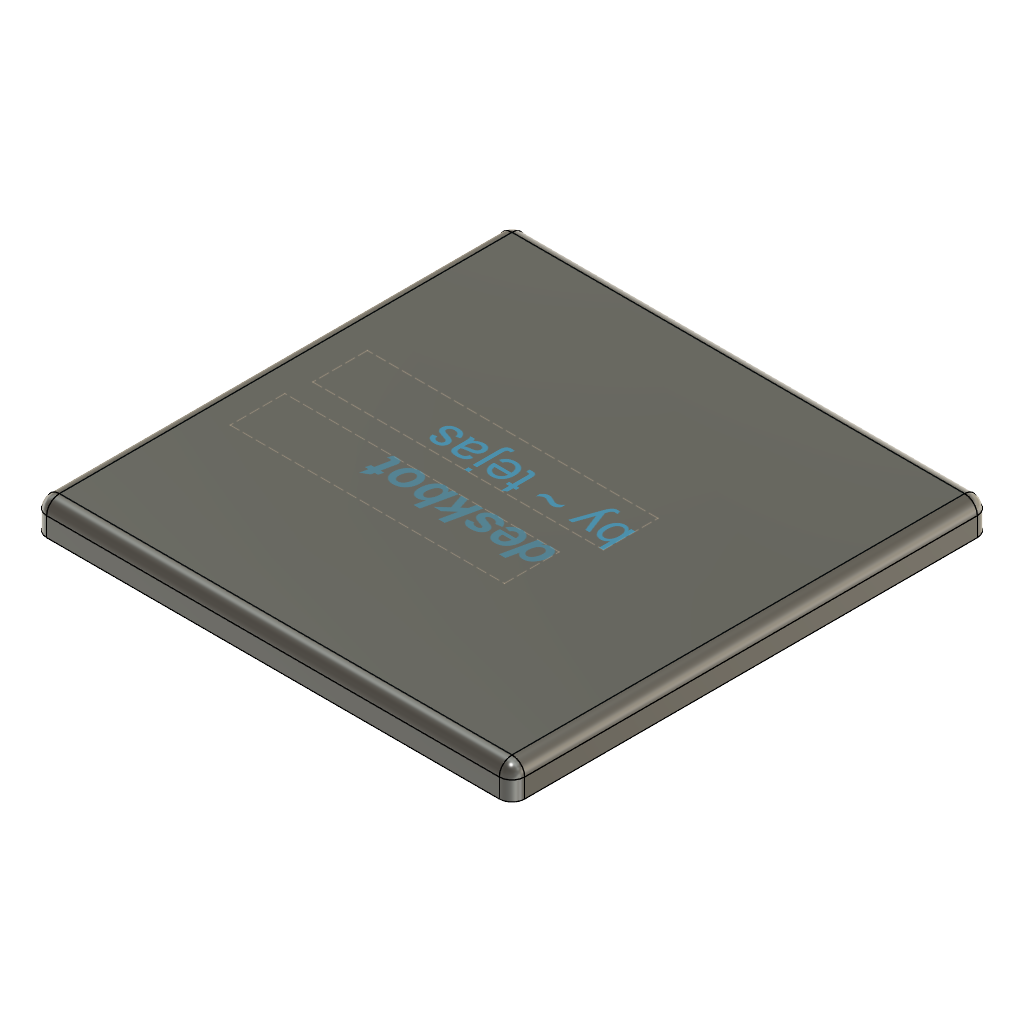
top+plate (Autodesk Fusion 360 design; units mm, degrees)
part number: 2026-10-28-19-44-58-231
Autodesk Fusion 360 part; units mm, degrees
sketch "Sketch1" plane through (0, 0, 0) normal (0, 0, 1) x (1, 0, 0)
  line L0 (-85.189, 83.3697) -> (64.811, 83.3697)
  line L1 (64.811, 83.3697) -> (64.811, -66.6303)
  line L2 (64.811, -66.6303) -> (-85.189, -66.6303)
  line L3 (-85.189, -66.6303) -> (-85.189, 83.3697)
  dimension "d1" = 150
  dimension "d2" = 150
  constraint horizontal L0
  constraint vertical L1
  constraint horizontal L2
  constraint vertical L3
  measures "d1" distance of L0.start L0.end
  measures "d2" distance of L0.start L2.end
extrude "Extrude1" add sketch "Sketch1" along normal blind 10
fillet "Fillet1" radius 4 1 edges at (64.811, -66.6303, 5)
fillet "Fillet2" radius 4 1 edges at (-85.189, -66.6303, 5)
fillet "Fillet3" radius 4 5 edges at (-85.189, 10.3697, 10) (-84.0174, -65.4588, 10) (-10.189, -66.6303, 10) (63.6394, -65.4588, 10) (64.811, 10.3697, 10)
fillet "Fillet4" radius 4 5 edges at (-85.189, 83.3697, 3) (-84.0174, 83.3697, 8.8284) (-10.189, 83.3697, 10) (63.6394, 83.3697, 8.8284) (64.811, 83.3697, 3)
sketch "Sketch2" plane through (0, 0, 10) normal (0, 0, 1) x (-1, 0, 0)
  line L0 (-60.811, -79.3697) -> (81.189, -79.3697)
  line L1 (81.189, -79.3697) -> (81.189, 62.6303)
  line L2 (81.189, 62.6303) -> (-60.811, 62.6303)
  line L3 (-60.811, 62.6303) -> (-60.811, -79.3697)
  line L4 (-13.0566, 0.107) -> (72.9886, 0.107) construction
  line L5 (72.9886, 0.107) -> (72.9886, 17.2304) construction
  line L6 (72.9886, 17.2304) -> (-13.0566, 17.2304) construction
  line L7 (-13.0566, 17.2304) -> (-13.0566, 0.107) construction
  dimension "d13" = 10
sketch "Sketch3" plane through (0, 0, 0) normal (0, 0, 1) x (1, 0, 0)
  line L0 (9.4179, 34.5679) -> (-81.7643, 34.5679) construction
  line L1 (-81.7643, 34.5679) -> (-81.7643, 17.4445) construction
  line L2 (-81.7643, 17.4445) -> (9.4179, 17.4445) construction
  line L3 (9.4179, 17.4445) -> (9.4179, 34.5679) construction
  dimension "d15" = 10
equation "d14 = 'deskbot'"
equation "d16 = 'by ~ tejas'"
